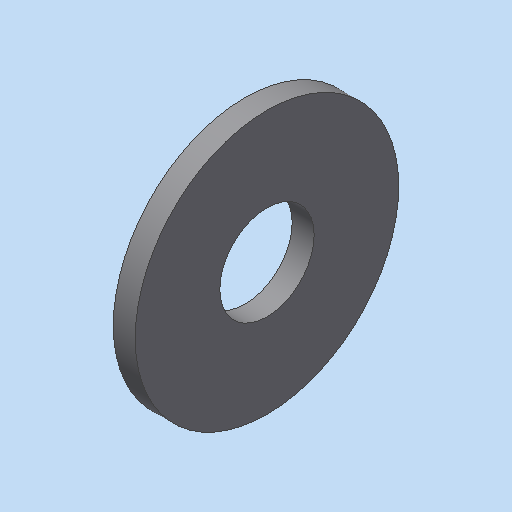
# Autodesk Inventor part: Scheibe_DIN_9021___4_3
Saved by Autodesk Inventor 2023.3 (Build 273359000, 359)
## iProperties
Shininess: 64.0
Length Units: 11269
Angle Units: 11279
Time Units: 11290
Mass Units: 11283
Length Display Precision: 3
Angle Display Precision: 2
Compacted: True
Part Number: Scheibe_DIN_9021___4_3
Document SubType Name: Modeling
Created: 2004-04-25
Description: =<RBPARTNOTITLE2>
Vendor: NORM8
Designer: C.Fischer
Manufacturer: Standard
Standards Organization: Custom
Density: 7.85 g/cm^3
Material: xStahl_AnP_Dummymaterial
Mass: 0.773816 g
Surface Area: 2.48359 cm^2
Volume: 0.0985753 cm^3
Appearance: RGB(178,178,178)
DOC_ID: 5 F45 Scheibe_DIN_9021___4_3
GAIN_REFID: 20__Scheibe_DIN_9021___4_3:470B9
Control State: 0
Master: False
Checked Out: False
CNS_NB: Scheibe DIN 9021 - 4.3
CNS_NN: DIN 9021
CNS_NT: Scheibe Aussendurchmesser = 3x Gewindenenndurchmesser
CNS_NBSYN: Scheibe DIN 9021 - $NENN.
CNS_LINA: Scheibe DIN 9021 - 4.3
CNS_NENN: 4.300
CNS_D: 4.000
CNS_DA: 4.300
CNS_DW: 12.000
CNS_H: 1.000
CNS_KT: X
PSOL_IDENT_0: {C:\partsolutions\data\23d-libs\bosch_bamberg\zubehoer\scheiben\din_9021.prj},142 {VTYP=3D},{NB=Sche
PSOL_IDENT_1: ibe DIN 9021 - 4.3},{NN=DIN 9021},{DATE=26.11.2003},{GEOMDATE=26.11.2003},{VERSION=v1},{LINEID=40},{
PSOL_IDENT_2: LINESUBID=-1},{WBVAR=}  {NB=Scheibe DIN 9021 - 4.3},{LINA=Scheibe DIN 9021 - 4.3},{KT=X},{IDNR=},{NE
PSOL_IDENT_3: NN=4.300},{D=4.000},{DA=4.300},{DW=12.000},{H=1.000}
DEF_STKID: T18678
Bezeichnung1: Scheibe DIN 9021 - 4.3
Bezeichnung2: Scheibe Aussendurchmesser = 3x Gewinden
RBPARTNOTITLE2: Karoseriescheibe, verzinkt
RBPARTNOTITLE1: Washer with large outside diameter, galvanised
RBPARTMADEOF: DIN 9021 - 4.3 - 100HV
RBDRAWINGMISSINGSPEC: --
AnP_Kategorie: 4
Density: 0.0
Volumn: 0.0
Area: 0.0
PropertySet Name: Model Information
Title: Scheibe DIN 9021 - 4.3
Author: C.Fischer
Keywords: =<RBPARTMADEOF>
Comments: =<RBSURFACE2>
Revision Number: 01
Autodesk Inventor part; units mm, degrees
sketch "Sketch_1" plane through (0, 0, 0) normal (0, 0, 1) x (1, 0, 0)
  line L0 (1, 0) -> (-2, 0)
  line L1 (0, 6) -> (0, 2.15)
  line L2 (0, 2.15) -> (1, 2.15)
  line L3 (1, 2.15) -> (1, 6)
  line L4 (1, 6) -> (0, 6)
  constraints: 10 end point
revolve "Revolution1" add sketch "Sketch_1" angle 360 about axis through (1, 0, 0) along (-1, 0, 0)
ref_plane "IP1_XY" through (0, 0, 0) normal (1, 0, 0) x (0, 0, -1)
ref_plane "IP1_YZ" through (0, 0, 0) normal (0, 0, -1) x (0, 1, 0)
ref_plane "IP2_XY" through (1, 0, 0) normal (1, 0, 0) x (0, 0, -1)
ref_plane "IP2_YZ" through (1, 0, 0) normal (0, 0, -1) x (0, 1, 0)
